Autodesk Fusion 360 part; units mm, degrees
(part 2 of 2)
sketch "スケッチ9" plane through (0, 0, 1) normal (0, 0, 1) x (-1, 0, 0)
  line L0 (-13, 12) -> (-13, 6)
  line L1 (-13, 6) -> (-6, 6)
  arc A0 (0, 0) -> (-6, 6) centre (-6, 0) ccw
  line L2 (0, 0) -> (0, -36)
  arc A1 (-6, -42) -> (0, -36) centre (-6, -36) ccw
  line L3 (-6, -42) -> (-13, -42)
  line L4 (-13, -42) -> (-13, -44)
  line L5 (59.8, -44) -> (59.8, -42)
  line L6 (59.8, -42) -> (52.8, -42)
  arc A2 (46.8, -36) -> (52.8, -42) centre (52.8, -36) ccw
  line L7 (46.8, -36) -> (46.8, 0)
  arc A3 (52.8, 6) -> (46.8, 0) centre (52.8, 0) ccw
  line L8 (52.8, 6) -> (59.8, 6)
  line L9 (59.8, 6) -> (59.8, 12)
  line L10 (59.8, 12) -> (-13, 12)
  circle A4 centre (44.3, -31.6) radius 1.5
  circle A5 centre (2.5, -31.6) radius 1.5
  circle A6 centre (44.3, -4.4) radius 1.5
  circle A7 centre (2.5, -4.4) radius 1.5
  line L11 (-13, -44) -> (59.8, -44)
  arc A8 (-13, -44) -> (59.8, -44) centre (23.4, -44) ccw
  constraint coincident L5.start L11.end
  constraint midpoint L11 A8.centre
  constraint coincident L4.end L11.start
extrude "押し出し6" add sketch "スケッチ9" against normal blind 1 separate body contours L11 A8 makes body 2
sketch "スケッチ10" plane through (0, 0, 0) normal (0, 0, -1) x (-1, 0, 0)
  arc A0 (59.8, 44) -> (-13, 44) centre (23.4, 44) ccw
  line L0 (-13, 44) -> (59.8, 44)
  line L1 (59.8, 44) -> (23.4, 44)
  line L2 (23.4, 44) -> (23.4, 89)
  circle A1 centre (23.4, 89) radius 25
  dimension "d41" = 45
  dimension "d42" = 50
  constraint coincident A0.start L0.end
  constraint coincident A0.centre L1.end
  constraint perpendicular L1 L2
  constraint coincident L2.end A1.centre
  measures "d41" distance of A0.centre L2.end
  measures "d42" diameter of A1
extrude "押し出し7" cut sketch "スケッチ10" against normal blind 5 contours A0 L2 A1 | A0 A1 | A0 L2 A1 bodies 2
sketch "スケッチ11" plane through (0, 0, 1) normal (0, 0, 1) x (-1, 0, 0)
  line L0 (-13, 12) -> (-13, 6)
  line L1 (-13, 6) -> (-6, 6)
  arc A0 (0, 0) -> (-6, 6) centre (-6, 0) ccw
  line L2 (0, 0) -> (0, -36)
  arc A1 (-6, -42) -> (0, -36) centre (-6, -36) ccw
  line L3 (-6, -42) -> (-13, -42)
  line L4 (-13, -42) -> (-13, -44)
  line L5 (-13, -44) -> (59.8, -44)
  line L6 (59.8, -44) -> (59.8, -42)
  line L7 (59.8, -42) -> (52.8, -42)
  arc A2 (46.8, -36) -> (52.8, -42) centre (52.8, -36) ccw
  line L8 (46.8, -36) -> (46.8, 0)
  arc A3 (52.8, 6) -> (46.8, 0) centre (52.8, 0) ccw
  line L9 (52.8, 6) -> (59.8, 6)
  line L10 (59.8, 6) -> (59.8, 12)
  line L11 (59.8, 12) -> (-13, 12)
  circle A4 centre (44.3, -31.6) radius 1.5
  circle A5 centre (2.5, -31.6) radius 1.5
  circle A6 centre (44.3, -4.4) radius 1.5
  circle A7 centre (2.5, -4.4) radius 1.5
  line L12 (59.8, 12) -> (-13, 12)
  line L13 (-13, 12) -> (-13, 17)
  line L14 (-13, 17) -> (59.8, 17)
  line L15 (59.8, 17) -> (59.8, 12)
  dimension "d38" = 5
  constraint horizontal L12
  constraint vertical L13
  constraint horizontal L14
  constraint vertical L15
  constraint coincident L10.end L11.start
  measures "d38" distance of L10.end L14.end
extrude "押し出し8" add sketch "スケッチ11" against normal blind 1 contours L11 L12 L13 L14 L15 bodies 1
fillet "フィレット4" radius 7.5 2 edges at (-43.605, 74.2773, 0.5) (-3.195, 74.2773, 0.5) on bodies 2
fillet "フィレット5" radius 2 4 edges at (13, -17, 0.5) (13, -6, 0.5) (-59.8, -17, 0.5) (-59.8, -6, 0.5) on bodies 1
fillet "フィレット6" radius 2 2 edges at (-59.8, 42, 0.5) (13, 42, 0.5) on bodies 1
sketch "スケッチ12" plane through (0, 0, 1) normal (0, 0, 1) x (-1, 0, 0)
  circle A0 centre (44.3, -31.6) radius 1.5
  circle A1 centre (2.5, -31.6) radius 1.5
  circle A2 centre (44.3, -4.4) radius 1.5
  circle A3 centre (2.5, -4.4) radius 1.5
  arc A4 (-11, -42) -> (-13, -44) centre (-11, -44) ccw
  line L0 (-13, -44) -> (59.8, -44)
  arc A5 (59.8, -44) -> (57.8, -42) centre (57.8, -44) ccw
  line L1 (57.8, -42) -> (52.8, -42)
  arc A6 (46.8, -36) -> (52.8, -42) centre (52.8, -36) ccw
  line L2 (46.8, -36) -> (46.8, 0)
  arc A7 (52.8, 6) -> (46.8, 0) centre (52.8, 0) ccw
  line L3 (52.8, 6) -> (57.8, 6)
  arc A8 (57.8, 6) -> (59.8, 8) centre (57.8, 8) ccw
  line L4 (59.8, 8) -> (59.8, 15)
  arc A9 (59.8, 15) -> (57.8, 17) centre (57.8, 15) ccw
  line L5 (57.8, 17) -> (-11, 17)
  arc A10 (-11, 17) -> (-13, 15) centre (-11, 15) ccw
  line L6 (-13, 15) -> (-13, 8)
  arc A11 (-13, 8) -> (-11, 6) centre (-11, 8) ccw
  line L7 (-11, 6) -> (-6, 6)
  arc A12 (0, 0) -> (-6, 6) centre (-6, 0) ccw
  line L8 (0, 0) -> (0, -36)
  arc A13 (-6, -42) -> (0, -36) centre (-6, -36) ccw
  line L9 (-6, -42) -> (-11, -42)
sketch "スケッチ13" plane through (0, 0, 1) normal (0, 0, 1) x (-1, 0, 0)
  circle A0 centre (44.3, -31.6) radius 1.5
  circle A1 centre (2.5, -31.6) radius 1.5
  circle A2 centre (44.3, -4.4) radius 1.5
  circle A3 centre (2.5, -4.4) radius 1.5
  arc A4 (-11, -42) -> (-13, -44) centre (-11, -44) ccw
  line L0 (-13, -44) -> (59.8, -44)
  arc A5 (59.8, -44) -> (57.8, -42) centre (57.8, -44) ccw
  line L1 (57.8, -42) -> (52.8, -42)
  arc A6 (46.8, -36) -> (52.8, -42) centre (52.8, -36) ccw
  line L2 (46.8, -36) -> (46.8, 0)
  arc A7 (52.8, 6) -> (46.8, 0) centre (52.8, 0) ccw
  line L3 (52.8, 6) -> (57.8, 6)
  arc A8 (57.8, 6) -> (59.8, 8) centre (57.8, 8) ccw
  line L4 (59.8, 8) -> (59.8, 15)
  arc A9 (59.8, 15) -> (57.8, 17) centre (57.8, 15) ccw
  line L5 (57.8, 17) -> (-11, 17)
  arc A10 (-11, 17) -> (-13, 15) centre (-11, 15) ccw
  line L6 (-13, 15) -> (-13, 8)
  arc A11 (-13, 8) -> (-11, 6) centre (-11, 8) ccw
  line L7 (-11, 6) -> (-6, 6)
  arc A12 (0, 0) -> (-6, 6) centre (-6, 0) ccw
  line L8 (0, 0) -> (0, -36)
  arc A13 (-6, -42) -> (0, -36) centre (-6, -36) ccw
  line L9 (-6, -42) -> (-11, -42)
  line L10 (59.8, 15) -> (59.8, 17)
  line L11 (59.8, 17) -> (23.4, 17)
  line L12 (23.4, 17) -> (23.4, 11)
  line L13 (23.4, 17) -> (23.9, 17)
  line L14 (23.9, 17) -> (22.9, 15.2679)
  line L15 (23.9, 17) -> (26.4, 17) construction
  line L16 (22.9, 17) -> (23.9, 15.2679)
  line L17 (23.4, 17) -> (22.9, 17)
  dimension "d49" = 0.5
  dimension "d50" = 120
  dimension "d51" = 2
  constraint coincident L4.end A9.start
  constraint tangent A9 L10
  constraint midpoint L5 L11.end
  constraint perpendicular L10 L11
  constraint perpendicular L5 L12
  constraint perpendicular L12 L13
  constraint horizontal L15
  constraint symmetric L11.end L12 L13.start
  constraint symmetric L12 L13.end L16.start
  constraint symmetric L12 L14.end L16.end
  measures "d49" distance of L11.end L13.end
  measures "d50" angle of L14 L15
  measures "d51" distance of L13.end L14.end
extrude "押し出し9" cut sketch "スケッチ13" against normal blind 1.5 contours L5 L12 L16 L17 | L5 L11 L12 L13 L14 bodies 1
sketch "スケッチ14" plane through (0, 0, 1) normal (0, 0, 1) x (-1, 0, 0)
  circle A0 centre (23.4, -42.425) radius 4.25
  arc A1 (46.7804, -31.9128) -> (43.1502, -29.3801) centre (44.3, -31.6) ccw
  line L0 (43.1502, -29.3801) -> (30.8479, -35.752)
  arc A2 (30.8479, -35.752) -> (15.9521, -35.752) centre (23.4, -42.425) ccw
  line L1 (15.9521, -35.752) -> (3.6498, -29.3801)
  arc A3 (3.6498, -29.3801) -> (0.0196, -31.9128) centre (2.5, -31.6) ccw
  line L2 (0.0196, -31.9128) -> (2.5196, -51.7378)
  arc A4 (2.5196, -51.7378) -> (6.0985, -53.6707) centre (5, -51.425) ccw
  line L3 (6.0985, -53.6707) -> (15.8007, -48.9251)
  arc A5 (15.8007, -48.9251) -> (30.9993, -48.9251) centre (23.4, -42.425) ccw
  line L4 (30.9993, -48.9251) -> (40.7015, -53.6707)
  arc A6 (40.7015, -53.6707) -> (44.2804, -51.7378) centre (41.8, -51.425) ccw
  line L5 (44.2804, -51.7378) -> (46.7804, -31.9128)
  line L6 (39.7572, -47.6427) -> (33.1962, -44.4336)
  arc A7 (33.1962, -44.4336) -> (33.1475, -40.1918) centre (23.4, -42.425) ccw
  line L7 (33.1475, -40.1918) -> (41.2243, -36.0085)
  line L8 (41.2243, -36.0085) -> (39.7572, -47.6427)
  line L9 (13.6038, -44.4336) -> (7.0428, -47.6427)
  line L10 (7.0428, -47.6427) -> (5.5757, -36.0085)
  line L11 (5.5757, -36.0085) -> (13.6525, -40.1918)
  arc A8 (13.6525, -40.1918) -> (13.6038, -44.4336) centre (23.4, -42.425) ccw
  circle A9 centre (2.5, -31.6) radius 1.5
  circle A10 centre (41.8, -51.425) radius 1.5
  circle A11 centre (44.3, -31.6) radius 1.5
  circle A12 centre (5, -51.425) radius 1.5
  circle A13 centre (23.4, -42.425) radius 7.5
  dimension "d58" = 15
  constraint concentric A0 A13
  measures "d58" diameter of A13
extrude "押し出し10" cut sketch "スケッチ14" against normal blind 2 contours A0 | A13 bodies 1 2
combine "結合1" operation add target body 2 tool bodies 1
sketch "スケッチ15" plane through (0, 0, 1) normal (0, 0, 1) x (-1, 0, 0)
  circle A0 centre (23.4, -42.425) radius 7.5
  circle A1 centre (2.5, -4.4) radius 1.5
  circle A2 centre (44.3, -4.4) radius 1.5
  circle A3 centre (2.5, -31.6) radius 1.5
  circle A4 centre (44.3, -31.6) radius 1.5
  arc A5 (59.8, -44) -> (57.8, -42) centre (57.8, -44) ccw
  line L0 (57.8, -42) -> (52.8, -42)
  arc A6 (46.8, -36) -> (52.8, -42) centre (52.8, -36) ccw
  line L1 (46.8, -36) -> (46.8, 0)
  arc A7 (52.8, 6) -> (46.8, 0) centre (52.8, 0) ccw
  line L2 (52.8, 6) -> (57.8, 6)
  arc A8 (57.8, 6) -> (59.8, 8) centre (57.8, 8) ccw
  line L3 (59.8, 8) -> (59.8, 15)
  arc A9 (59.8, 15) -> (57.8, 17) centre (57.8, 15) ccw
  line L4 (57.8, 17) -> (23.9, 17)
  line L5 (23.9, 17) -> (23.4, 16.134)
  line L6 (23.4, 16.134) -> (22.9, 17)
  line L7 (22.9, 17) -> (-11, 17)
  arc A10 (-11, 17) -> (-13, 15) centre (-11, 15) ccw
  line L8 (-13, 15) -> (-13, 8)
  arc A11 (-13, 8) -> (-11, 6) centre (-11, 8) ccw
  line L9 (-11, 6) -> (-6, 6)
  arc A12 (0, 0) -> (-6, 6) centre (-6, 0) ccw
  line L10 (0, 0) -> (0, -36)
  arc A13 (-6, -42) -> (0, -36) centre (-6, -36) ccw
  line L11 (-6, -42) -> (-11, -42)
  arc A14 (-11, -42) -> (-13, -44) centre (-11, -44) ccw
  arc A15 (-13, -44) -> (-2.8224, -69.2457) centre (23.4, -44) ccw
  arc A16 (-2.8224, -69.2457) -> (7.3851, -69.8031) centre (2.5806, -64.044) ccw
  arc A17 (39.4149, -69.8031) -> (7.3851, -69.8031) centre (23.4, -89) ccw
  arc A18 (39.4149, -69.8031) -> (49.6224, -69.2457) centre (44.2194, -64.044) ccw
  arc A19 (49.6224, -69.2457) -> (59.8, -44) centre (23.4, -44) ccw
  line L12 (2.5, -31.6) -> (2.5, -51.425)
  line L13 (2.5, -51.425) -> (5, -51.425)
  line L14 (5, -51.425) -> (5, -51.8549)
  line L15 (5, -51.8549) -> (2.5, -51.8549)
  line L16 (2.5, -51.8549) -> (2.5, -51.425)
  line L17 (23.4, -42.425) -> (23.4, -46.4898)
  circle A20 centre (5, -51.425) radius 1.5
  circle A21 centre (41.8, -51.425) radius 1.5
  dimension "d61" = 19.825
  dimension "d62" = 2.5
  dimension "d63" = 3
  constraint coincident A3.centre L12.start
  constraint vertical L12
  constraint horizontal L13
  constraint vertical L14
  constraint horizontal L15
  constraint vertical L16
  constraint coincident A0.centre L17.start
  constraint vertical L17
  constraint coincident L13.end L14.start
  constraint symmetric L17 A20 A21
  measures "d61" distance of A3.centre L12.end
  measures "d62" distance of L12.end L13.end
  measures "d63" diameter of A20
extrude "押し出し11" cut sketch "スケッチ15" against normal blind 2 contours L13 L14 L15 A20 | L13 L14 L15 A20 | A21 bodies 2
sketch "スケッチ16" plane through (0, 0, 1) normal (0, 0, 1) x (-1, 0, 0)
  circle A0 centre (41.8, -51.425) radius 1.5
  circle A1 centre (5, -51.425) radius 1.5
  circle A2 centre (23.4, -42.425) radius 7.5
  circle A3 centre (2.5, -4.4) radius 1.5
  circle A4 centre (44.3, -4.4) radius 1.5
  circle A5 centre (2.5, -31.6) radius 1.5
  circle A6 centre (44.3, -31.6) radius 1.5
  arc A7 (59.8, -44) -> (57.8, -42) centre (57.8, -44) ccw
  line L0 (57.8, -42) -> (52.8, -42)
  arc A8 (46.8, -36) -> (52.8, -42) centre (52.8, -36) ccw
  line L1 (46.8, -36) -> (46.8, 0)
  arc A9 (52.8, 6) -> (46.8, 0) centre (52.8, 0) ccw
  line L2 (52.8, 6) -> (57.8, 6)
  arc A10 (57.8, 6) -> (59.8, 8) centre (57.8, 8) ccw
  line L3 (59.8, 8) -> (59.8, 15)
  arc A11 (59.8, 15) -> (57.8, 17) centre (57.8, 15) ccw
  line L4 (57.8, 17) -> (23.9, 17)
  line L5 (23.9, 17) -> (23.4, 16.134)
  line L6 (23.4, 16.134) -> (22.9, 17)
  line L7 (22.9, 17) -> (-11, 17)
  arc A12 (-11, 17) -> (-13, 15) centre (-11, 15) ccw
  line L8 (-13, 15) -> (-13, 8)
  arc A13 (-13, 8) -> (-11, 6) centre (-11, 8) ccw
  line L9 (-11, 6) -> (-6, 6)
  arc A14 (0, 0) -> (-6, 6) centre (-6, 0) ccw
  line L10 (0, 0) -> (0, -36)
  arc A15 (-6, -42) -> (0, -36) centre (-6, -36) ccw
  line L11 (-6, -42) -> (-11, -42)
  arc A16 (-11, -42) -> (-13, -44) centre (-11, -44) ccw
  arc A17 (-13, -44) -> (-2.8224, -69.2457) centre (23.4, -44) ccw
  arc A18 (-2.8224, -69.2457) -> (7.3851, -69.8031) centre (2.5806, -64.044) ccw
  arc A19 (39.4149, -69.8031) -> (7.3851, -69.8031) centre (23.4, -89) ccw
  arc A20 (39.4149, -69.8031) -> (49.6224, -69.2457) centre (44.2194, -64.044) ccw
  arc A21 (49.6224, -69.2457) -> (59.8, -44) centre (23.4, -44) ccw
  line L12 (23.4, -42.425) -> (23.4, -49)
  line L13 (41.8, -51.425) -> (41.8, -50.425)
  line L14 (41.8, -50.425) -> (51.8, -50.425)
  line L15 (51.8, -50.425) -> (53.1497, -56.2712)
  line L16 (51.8, -50.425) -> (59.8, -50.425) construction
  line L17 (51.6882, -56.6086) -> (60.4426, -56.6086) construction
  line L18 (53.1497, -56.2712) -> (51.6882, -56.6086)
  line L19 (51.6882, -56.6086) -> (54.6113, -55.9338)
  line L20 (54.6113, -55.9338) -> (53.2616, -50.0876)
  line L21 (53.2616, -50.0876) -> (50.3384, -50.7624)
  line L22 (50.3384, -50.7624) -> (51.6882, -56.6086)
  line L23 (-4.8882, -56.6086) -> (-7.8113, -55.9338)
  line L24 (-6.4616, -50.0876) -> (-3.5384, -50.7624)
  line L25 (-7.8113, -55.9338) -> (-6.4616, -50.0876)
  line L26 (-5, -50.425) -> (-6.3497, -56.2712)
  line L27 (-3.5384, -50.7624) -> (-4.8882, -56.6086)
  line L28 (-6.3497, -56.2712) -> (-4.8882, -56.6086)
  arc A22 (49.6224, -69.2457) -> (59.8, -44) centre (23.4, -44) ccw
  dimension "d66" = 1
  dimension "d67" = 10
  dimension "d68" = 77
  dimension "d69" = 6
  dimension "d70" = 1.5
  dimension "d75" = 3
  dimension "d76" = 6
  dimension "d77" = 3
  constraint coincident A2.centre L12.start
  constraint vertical L12
  constraint coincident A0.centre L13.start
  constraint vertical L13
  constraint perpendicular L13 L14
  constraint horizontal L16
  constraint horizontal L17
  constraint perpendicular L15 L18
  constraint perpendicular L15 L19
  constraint perpendicular L19 L20
  constraint perpendicular L20 L21
  constraint symmetric L12 L14.end L26.start
  constraint symmetric L12 L15.end L26.end
  constraint symmetric L12 L17.start L23.start
  constraint symmetric L12 L19.end L23.end
  constraint symmetric L12 L20.end L24.start
  constraint symmetric L12 L21.end L24.end
  measures "d66" distance of A0.centre L13.end
  measures "d67" distance of L13.end L14.end
  measures "d68" angle of L15 L16
  measures "d69" distance of L14.end L15.end
  measures "d70" distance of L15.end L17.start
  measures "d75" distance of L17.start L19.end
  measures "d76" distance of L19.end L20.end
  measures "d77" distance of L20.end L21.end
extrude "押し出し12" cut sketch "スケッチ16" against normal blind 8 contours L15 L19 L20 L21 | L15 L18 L19 L21 L22 | L23 L24 L26 L27 L28 | L23 L24 L25 L26 bodies 2
sketch "スケッチ17" plane through (0, 0, 1) normal (0, 0, 1) x (-1, 0, 0)
  line L0 (-3.5384, -50.7624) -> (-4.8882, -56.6086)
  line L1 (-4.8882, -56.6086) -> (-7.8113, -55.9338)
  line L2 (-7.8113, -55.9338) -> (-6.4616, -50.0876)
  line L3 (-6.4616, -50.0876) -> (-3.5384, -50.7624)
  line L4 (54.6113, -55.9338) -> (51.6882, -56.6086)
  line L5 (51.6882, -56.6086) -> (50.3384, -50.7624)
  line L6 (50.3384, -50.7624) -> (53.2616, -50.0876)
  line L7 (53.2616, -50.0876) -> (54.6113, -55.9338)
  circle A0 centre (41.8, -51.425) radius 1.5
  circle A1 centre (5, -51.425) radius 1.5
  circle A2 centre (23.4, -42.425) radius 7.5
  circle A3 centre (2.5, -31.6) radius 1.5
  circle A4 centre (44.3, -31.6) radius 1.5
  circle A5 centre (2.5, -4.4) radius 1.5
  circle A6 centre (44.3, -4.4) radius 1.5
  arc A7 (59.8, -44) -> (57.8, -42) centre (57.8, -44) ccw
  line L8 (57.8, -42) -> (52.8, -42)
  arc A8 (46.8, -36) -> (52.8, -42) centre (52.8, -36) ccw
  line L9 (46.8, -36) -> (46.8, 0)
  arc A9 (52.8, 6) -> (46.8, 0) centre (52.8, 0) ccw
  line L10 (52.8, 6) -> (57.8, 6)
  arc A10 (57.8, 6) -> (59.8, 8) centre (57.8, 8) ccw
  line L11 (59.8, 8) -> (59.8, 15)
  arc A11 (59.8, 15) -> (57.8, 17) centre (57.8, 15) ccw
  line L12 (57.8, 17) -> (23.9, 17)
  line L13 (23.9, 17) -> (23.4, 16.134)
  line L14 (23.4, 16.134) -> (22.9, 17)
  line L15 (22.9, 17) -> (-11, 17)
  arc A12 (-11, 17) -> (-13, 15) centre (-11, 15) ccw
  line L16 (-13, 15) -> (-13, 8)
  arc A13 (-13, 8) -> (-11, 6) centre (-11, 8) ccw
  line L17 (-11, 6) -> (-6, 6)
  arc A14 (0, 0) -> (-6, 6) centre (-6, 0) ccw
  line L18 (0, 0) -> (0, -36)
  arc A15 (-6, -42) -> (0, -36) centre (-6, -36) ccw
  line L19 (-6, -42) -> (-11, -42)
  arc A16 (-11, -42) -> (-13, -44) centre (-11, -44) ccw
  arc A17 (-13, -44) -> (-2.8224, -69.2457) centre (23.4, -44) ccw
  arc A18 (-2.8224, -69.2457) -> (7.3851, -69.8031) centre (2.5806, -64.044) ccw
  arc A19 (39.4149, -69.8031) -> (7.3851, -69.8031) centre (23.4, -89) ccw
  arc A20 (39.4149, -69.8031) -> (49.6224, -69.2457) centre (44.2194, -64.044) ccw
  arc A21 (49.6224, -69.2457) -> (59.8, -44) centre (23.4, -44) ccw
  line L20 (41.8, -51.425) -> (41.8, -63.425)
  line L21 (41.8, -63.425) -> (46.8, -63.425)
  line L22 (46.8, -63.425) -> (47.4339, -64.7845)
  line L23 (46.8, -63.425) -> (48.3, -63.425) construction
  line L24 (47.4339, -64.7845) -> (46.1661, -62.0655)
  line L25 (46.1661, -62.0655) -> (40.7282, -64.6012)
  line L26 (46.1661, -62.0655) -> (52.287, -62.0655) construction
  line L27 (47.4339, -64.7845) -> (41.9961, -67.3202)
  line L28 (41.9961, -67.3202) -> (40.7282, -64.6012)
  line L29 (23.4, -42.425) -> (23.4, -45)
  line L30 (-0.6339, -64.7845) -> (0.6339, -62.0655)
  line L31 (0, -63.425) -> (-0.6339, -64.7845)
  line L32 (-0.6339, -64.7845) -> (4.8039, -67.3202)
  line L33 (5, -63.425) -> (0, -63.425)
  line L34 (4.8039, -67.3202) -> (6.0718, -64.6012)
  line L35 (0, -63.425) -> (-1.5, -63.425) construction
  line L36 (0.6339, -62.0655) -> (6.0718, -64.6012)
  point P0 (2.5806, -64.044)
  dimension "d78" = 12
  dimension "d79" = 5
  dimension "d80" = 65
  dimension "d81" = 1.5
  dimension "d82" = 3
  dimension "d83" = 155
  dimension "d84" = 6
  dimension "d85" = 6
  constraint coincident A0.centre L20.start
  constraint vertical L20
  constraint perpendicular L20 L21
  constraint horizontal L23
  constraint parallel L22 L24
  constraint horizontal L26
  constraint perpendicular L22 L27
  constraint coincident A2.centre L29.start
  constraint vertical L29
  constraint symmetric A20.centre L29 P0
  constraint symmetric L20.end L29 L33.start
  constraint symmetric L21.end L29 L31.start
  constraint symmetric L22.end L29 L30.start
  constraint symmetric L23.end L29 L35.end
  constraint symmetric L24.end L29 L30.end
  constraint symmetric L25.end L29 L34.end
  constraint symmetric L27.end L29 L32.end
  measures "d78" distance of A0.centre L20.end
  measures "d79" distance of L20.end L21.end
  measures "d80" angle of L22 L23
  measures "d81" distance of L21.end L22.end
  measures "d82" distance of L22.end L24.end
  measures "d83" angle of L25 L26
  measures "d84" distance of L24.end L25.end
  measures "d85" distance of L22.end L27.end
extrude "押し出し13" cut sketch "スケッチ17" against normal blind 4 contours L21 L24 L25 | L21 L22 L24 L25 L27 L28 | L30 L31 L32 L33 L34 L36 | L30 L33 L36 bodies 2
sketch "スケッチ18" plane through (0, 0, 1) normal (0, 0, 1) x (-1, 0, 0)
  line L0 (40.7282, -64.6012) -> (46.1661, -62.0655)
  line L1 (46.1661, -62.0655) -> (47.4339, -64.7845)
  line L2 (47.4339, -64.7845) -> (41.9961, -67.3202)
  line L3 (41.9961, -67.3202) -> (40.7282, -64.6012)
  line L4 (4.8039, -67.3202) -> (-0.6339, -64.7845)
  line L5 (-0.6339, -64.7845) -> (0.6339, -62.0655)
  line L6 (0.6339, -62.0655) -> (6.0718, -64.6012)
  line L7 (6.0718, -64.6012) -> (4.8039, -67.3202)
  line L8 (-3.5384, -50.7624) -> (-4.8882, -56.6086)
  line L9 (-4.8882, -56.6086) -> (-7.8113, -55.9338)
  line L10 (-7.8113, -55.9338) -> (-6.4616, -50.0876)
  line L11 (-6.4616, -50.0876) -> (-3.5384, -50.7624)
  line L12 (54.6113, -55.9338) -> (51.6882, -56.6086)
  line L13 (51.6882, -56.6086) -> (50.3384, -50.7624)
  line L14 (50.3384, -50.7624) -> (53.2616, -50.0876)
  line L15 (53.2616, -50.0876) -> (54.6113, -55.9338)
  circle A0 centre (41.8, -51.425) radius 1.5
  circle A1 centre (5, -51.425) radius 1.5
  circle A2 centre (23.4, -42.425) radius 7.5
  circle A3 centre (2.5, -31.6) radius 1.5
  circle A4 centre (44.3, -31.6) radius 1.5
  circle A5 centre (2.5, -4.4) radius 1.5
  circle A6 centre (44.3, -4.4) radius 1.5
  arc A7 (59.8, -44) -> (57.8, -42) centre (57.8, -44) ccw
  line L16 (57.8, -42) -> (52.8, -42)
  arc A8 (46.8, -36) -> (52.8, -42) centre (52.8, -36) ccw
  line L17 (46.8, -36) -> (46.8, 0)
  arc A9 (52.8, 6) -> (46.8, 0) centre (52.8, 0) ccw
  line L18 (52.8, 6) -> (57.8, 6)
  arc A10 (57.8, 6) -> (59.8, 8) centre (57.8, 8) ccw
  line L19 (59.8, 8) -> (59.8, 15)
  arc A11 (59.8, 15) -> (57.8, 17) centre (57.8, 15) ccw
  line L20 (57.8, 17) -> (23.9, 17)
  line L21 (23.9, 17) -> (23.4, 16.134)
  line L22 (23.4, 16.134) -> (22.9, 17)
  line L23 (22.9, 17) -> (-11, 17)
  arc A12 (-11, 17) -> (-13, 15) centre (-11, 15) ccw
  line L24 (-13, 15) -> (-13, 8)
  arc A13 (-13, 8) -> (-11, 6) centre (-11, 8) ccw
  line L25 (-11, 6) -> (-6, 6)
  arc A14 (0, 0) -> (-6, 6) centre (-6, 0) ccw
  line L26 (0, 0) -> (0, -36)
  arc A15 (-6, -42) -> (0, -36) centre (-6, -36) ccw
  line L27 (-6, -42) -> (-11, -42)
  arc A16 (-11, -42) -> (-13, -44) centre (-11, -44) ccw
  arc A17 (-13, -44) -> (-2.8224, -69.2457) centre (23.4, -44) ccw
  arc A18 (-2.8224, -69.2457) -> (7.3851, -69.8031) centre (2.5806, -64.044) ccw
  arc A19 (39.4149, -69.8031) -> (7.3851, -69.8031) centre (23.4, -89) ccw
  arc A20 (39.4149, -69.8031) -> (49.6224, -69.2457) centre (44.2194, -64.044) ccw
  arc A21 (49.6224, -69.2457) -> (59.8, -44) centre (23.4, -44) ccw
sketch "スケッチ19" plane through (0, 0, 1) normal (0, 0, 1) x (-1, 0, 0)
  line L0 (40.7282, -64.6012) -> (46.1661, -62.0655)
  line L1 (46.1661, -62.0655) -> (47.4339, -64.7845)
  line L2 (47.4339, -64.7845) -> (41.9961, -67.3202)
  line L3 (41.9961, -67.3202) -> (40.7282, -64.6012)
  line L4 (4.8039, -67.3202) -> (-0.6339, -64.7845)
  line L5 (-0.6339, -64.7845) -> (0.6339, -62.0655)
  line L6 (0.6339, -62.0655) -> (6.0718, -64.6012)
  line L7 (6.0718, -64.6012) -> (4.8039, -67.3202)
  line L8 (-3.5384, -50.7624) -> (-4.8882, -56.6086)
  line L9 (-4.8882, -56.6086) -> (-7.8113, -55.9338)
  line L10 (-7.8113, -55.9338) -> (-6.4616, -50.0876)
  line L11 (-6.4616, -50.0876) -> (-3.5384, -50.7624)
  line L12 (54.6113, -55.9338) -> (51.6882, -56.6086)
  line L13 (51.6882, -56.6086) -> (50.3384, -50.7624)
  line L14 (50.3384, -50.7624) -> (53.2616, -50.0876)
  line L15 (53.2616, -50.0876) -> (54.6113, -55.9338)
  circle A0 centre (41.8, -51.425) radius 1.5
  circle A1 centre (5, -51.425) radius 1.5
  circle A2 centre (23.4, -42.425) radius 7.5
  circle A3 centre (2.5, -31.6) radius 1.5
  circle A4 centre (44.3, -31.6) radius 1.5
  circle A5 centre (2.5, -4.4) radius 1.5
  circle A6 centre (44.3, -4.4) radius 1.5
  arc A7 (59.8, -44) -> (57.8, -42) centre (57.8, -44) ccw
  line L16 (57.8, -42) -> (52.8, -42)
  arc A8 (46.8, -36) -> (52.8, -42) centre (52.8, -36) ccw
  line L17 (46.8, -36) -> (46.8, 0)
  arc A9 (52.8, 6) -> (46.8, 0) centre (52.8, 0) ccw
  line L18 (52.8, 6) -> (57.8, 6)
  arc A10 (57.8, 6) -> (59.8, 8) centre (57.8, 8) ccw
  line L19 (59.8, 8) -> (59.8, 15)
  arc A11 (59.8, 15) -> (57.8, 17) centre (57.8, 15) ccw
  line L20 (57.8, 17) -> (23.9, 17)
  line L21 (23.9, 17) -> (23.4, 16.134)
  line L22 (23.4, 16.134) -> (22.9, 17)
  line L23 (22.9, 17) -> (-11, 17)
  arc A12 (-11, 17) -> (-13, 15) centre (-11, 15) ccw
  line L24 (-13, 15) -> (-13, 8)
  arc A13 (-13, 8) -> (-11, 6) centre (-11, 8) ccw
  line L25 (-11, 6) -> (-6, 6)
  arc A14 (0, 0) -> (-6, 6) centre (-6, 0) ccw
  line L26 (0, 0) -> (0, -36)
  arc A15 (-6, -42) -> (0, -36) centre (-6, -36) ccw
  line L27 (-6, -42) -> (-11, -42)
  arc A16 (-11, -42) -> (-13, -44) centre (-11, -44) ccw
  arc A17 (-13, -44) -> (-2.8224, -69.2457) centre (23.4, -44) ccw
  arc A18 (-2.8224, -69.2457) -> (7.3851, -69.8031) centre (2.5806, -64.044) ccw
  arc A19 (39.4149, -69.8031) -> (7.3851, -69.8031) centre (23.4, -89) ccw
  arc A20 (39.4149, -69.8031) -> (49.6224, -69.2457) centre (44.2194, -64.044) ccw
  arc A21 (49.6224, -69.2457) -> (59.8, -44) centre (23.4, -44) ccw
sketch "スケッチ7" plane through (0, 0, 1) normal (0, 0, 1) x (-1, 0, 0)
  line L0 (23.4, 11.134) -> (22.9, 12)
  line L1 (22.9, 12) -> (-12.5, 12)
  line L2 (-12.5, 12) -> (-12.5, 6)
  line L3 (-12.5, 6) -> (-6, 6)
  arc A0 (0, 0) -> (-6, 6) centre (-6, 0) ccw
  line L4 (0, 0) -> (0, -36)
  line L5 (46.8, -36) -> (46.8, 0)
  arc A1 (52.8, 6) -> (46.8, 0) centre (52.8, 0) ccw
  line L6 (52.8, 6) -> (59.3, 6)
  line L7 (59.3, 6) -> (59.3, 12)
  line L8 (59.3, 12) -> (23.9, 12)
  line L9 (23.9, 12) -> (23.4, 11.134)
  line L10 (3, -22) -> (3, -27)
  line L11 (3, -27) -> (2.5, -27)
  line L12 (2.5, -27) -> (2, -27)
  line L13 (2, -27) -> (2, -22)
  line L14 (2, -22) -> (3, -22)
  line L15 (42.8, -2.2) -> (42.8, -1.2)
  line L16 (42.8, -1.2) -> (45.8, -1.2)
  line L17 (45.8, -1.2) -> (45.8, -2.2)
  line L18 (45.8, -2.2) -> (42.8, -2.2)
  circle A2 centre (44.3, -31.6) radius 1.5
  line L19 (43.8, -27) -> (43.8, -22)
  line L20 (43.8, -22) -> (44.8, -22)
  line L21 (44.8, -22) -> (44.8, -27)
  line L22 (44.8, -27) -> (44.3, -27)
  line L23 (44.3, -27) -> (43.8, -27)
  line L24 (2, -9) -> (2.5, -9)
  line L25 (2.5, -9) -> (3, -9)
  line L26 (3, -9) -> (3, -14)
  line L27 (3, -14) -> (2, -14)
  line L28 (2, -14) -> (2, -9)
  circle A3 centre (2.5, -31.6) radius 1.5
  line L29 (1, -2.2) -> (1, -1.2)
  line L30 (1, -1.2) -> (4, -1.2)
  line L31 (4, -1.2) -> (4, -2.2)
  line L32 (4, -2.2) -> (1, -2.2)
  circle A4 centre (44.3, -4.4) radius 1.5
  line L33 (42.8, -34.8) -> (42.8, -33.8)
  line L34 (42.8, -33.8) -> (45.8, -33.8)
  line L35 (45.8, -33.8) -> (45.8, -34.8)
  line L36 (45.8, -34.8) -> (42.8, -34.8)
  line L37 (44.8, -14) -> (43.8, -14)
  line L38 (43.8, -14) -> (43.8, -9)
  line L39 (43.8, -9) -> (44.3, -9)
  line L40 (44.3, -9) -> (44.8, -9)
  line L41 (44.8, -9) -> (44.8, -14)
  circle A5 centre (2.5, -4.4) radius 1.5
  line L42 (4, -33.8) -> (4, -34.8)
  line L43 (4, -34.8) -> (1, -34.8)
  line L44 (1, -34.8) -> (1, -33.8)
  line L45 (1, -33.8) -> (4, -33.8)
  arc A6 (-6, -42) -> (0, -36) centre (-6, -36) ccw
  line L46 (-6, -42) -> (-12.5, -42)
  line L47 (-12.5, -42) -> (-12.5, -48)
  line L48 (-12.5, -48) -> (59.3, -48)
  line L49 (59.3, -48) -> (59.3, -42)
  line L50 (59.3, -42) -> (52.8, -42)
  arc A7 (46.8, -36) -> (52.8, -42) centre (52.8, -36) ccw
sketch "スケッチ2" plane through (0, 0, 1) normal (0, 0, 1) x (-1, 0, 0)
  line L0 (0, -44) -> (48.8, -44)
  line L1 (48.8, -44) -> (48.8, 0)
  line L2 (48.8, 0) -> (0, 0)
  line L3 (0, 0) -> (0, -44)
  line L4 (48.8, -44) -> (0, -44)
  line L5 (0, -44) -> (0, -52)
  line L6 (0, -52) -> (48.8, -52)
  line L7 (48.8, -52) -> (48.8, -44)
  dimension "d5" = 8
  constraint horizontal L4
  constraint vertical L5
  constraint horizontal L6
  constraint vertical L7
  constraint coincident L0.end L1.start
  measures "d5" distance of L0.end L6.end
sketch "スケッチ3" plane through (0, 0, 1) normal (0, 0, 1) x (-1, 0, 0)

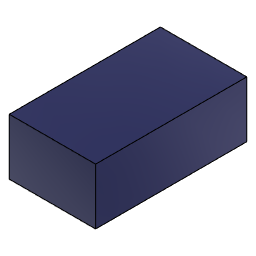
design "Lipoバッテリー"
Autodesk Fusion 360 part; units mm, degrees
sketch "スケッチ1" plane through (0, 0, 0) normal (0, 0, 1) x (1, 0, 0)
  line L0 (0, 0) -> (-20, 0)
  line L1 (-20, 0) -> (-20, -35)
  line L2 (-20, -35) -> (0, -35)
  line L3 (0, -35) -> (0, 0)
  dimension "d1" = 20
  dimension "d2" = 35
  constraint horizontal L0
  constraint vertical L1
  constraint horizontal L2
  constraint vertical L3
  constraint coincident L0.start L3.end
  measures "d1" distance of L0.start L0.end
  measures "d2" distance of L0.start L2.end
extrude "押し出し1" add sketch "スケッチ1" along normal blind 13
